f3d-ac5eee68aa18 (Autodesk Fusion 360 design; units mm, degrees)
Autodesk Fusion 360 part; units mm, degrees
ref_plane "WorkPlane1" through (0, 0, 0) normal (0, 1, 0) x (0, 0, 1) in component "ДСП 16 — горизонталь"
sketch "Sketch1" plane through (0, 0, 0) normal (0, 1, 0) x (1, 0, 0) in component "ДСП 16 — горизонталь"
  line L0 (150, -2) -> (850, -2)
  arc A0 (850, -298) -> (850, -2) centre (850, -150) ccw
  line L1 (850, -298) -> (150, -298)
  arc A1 (150, -2) -> (150, -298) centre (150, -150) ccw
extrude "ДСП 16 — горизонталь" add sketch "Sketch1" along normal blind 16 makes body 1 in component "ДСП 16 — горизонталь"
ref_plane "WorkPlane2" through (0, 0, 0) normal (0, 1, 0) x (0, 0, 1) in component "ДСП 16 — горизонталь"
sketch "Sketch2" plane through (0, 0, 0) normal (0, 1, 0) x (1, 0, 0) in component "ДСП 16 — горизонталь"
  line L0 (208.1, 3) -> (208.1, -37)
  line L1 (208.1, -37) -> (191.9, -37)
  line L2 (191.9, -37) -> (191.9, 3)
  line L3 (191.9, 3) -> (208.1, 3)
  line L4 (408.1, 3) -> (408.1, -37)
  line L5 (408.1, -37) -> (391.9, -37)
  line L6 (391.9, -37) -> (391.9, 3)
  line L7 (391.9, 3) -> (408.1, 3)
  line L8 (499.1, 3) -> (499.1, -37)
  line L9 (499.1, -37) -> (482.9, -37)
  line L10 (482.9, -37) -> (482.9, 3)
  line L11 (482.9, 3) -> (499.1, 3)
  line L12 (517.1, 3) -> (517.1, -37)
  line L13 (517.1, -37) -> (500.9, -37)
  line L14 (500.9, -37) -> (500.9, 3)
  line L15 (500.9, 3) -> (517.1, 3)
  line L16 (608.1, 3) -> (608.1, -37)
  line L17 (608.1, -37) -> (591.9, -37)
  line L18 (591.9, -37) -> (591.9, 3)
  line L19 (591.9, 3) -> (608.1, 3)
  line L20 (808.1, 3) -> (808.1, -37)
  line L21 (808.1, -37) -> (791.9, -37)
  line L22 (791.9, -37) -> (791.9, 3)
  line L23 (791.9, 3) -> (808.1, 3)
  line L24 (191.9, -303) -> (191.9, -263)
  line L25 (191.9, -263) -> (208.1, -263)
  line L26 (208.1, -263) -> (208.1, -303)
  line L27 (208.1, -303) -> (191.9, -303)
  line L28 (391.9, -303) -> (391.9, -263)
  line L29 (391.9, -263) -> (408.1, -263)
  line L30 (408.1, -263) -> (408.1, -303)
  line L31 (408.1, -303) -> (391.9, -303)
  line L32 (482.9, -303) -> (482.9, -263)
  line L33 (482.9, -263) -> (499.1, -263)
  line L34 (499.1, -263) -> (499.1, -303)
  line L35 (499.1, -303) -> (482.9, -303)
  line L36 (500.9, -303) -> (500.9, -263)
  line L37 (500.9, -263) -> (517.1, -263)
  line L38 (517.1, -263) -> (517.1, -303)
  line L39 (517.1, -303) -> (500.9, -303)
  line L40 (591.9, -303) -> (591.9, -263)
  line L41 (591.9, -263) -> (608.1, -263)
  line L42 (608.1, -263) -> (608.1, -303)
  line L43 (608.1, -303) -> (591.9, -303)
  line L44 (791.9, -303) -> (791.9, -263)
  line L45 (791.9, -263) -> (808.1, -263)
  line L46 (808.1, -263) -> (808.1, -303)
  line L47 (808.1, -303) -> (791.9, -303)
  line L48 (933.5148, -21.5481) -> (913.5148, -56.1891)
  line L49 (913.5148, -56.1891) -> (899.4852, -48.0891)
  line L50 (899.4852, -48.0891) -> (919.4852, -13.4481)
  line L51 (919.4852, -13.4481) -> (933.5148, -21.5481)
  line L52 (1003, -158.1) -> (963, -158.1)
  line L53 (963, -158.1) -> (963, -141.9)
  line L54 (963, -141.9) -> (1003, -141.9)
  line L55 (1003, -141.9) -> (1003, -158.1)
  line L56 (919.4852, -286.5519) -> (899.4852, -251.9109)
  line L57 (899.4852, -251.9109) -> (913.5148, -243.8109)
  line L58 (913.5148, -243.8109) -> (933.5148, -278.4519)
  line L59 (933.5148, -278.4519) -> (919.4852, -286.5519)
  line L60 (66.4852, -278.4519) -> (86.4852, -243.8109)
  line L61 (86.4852, -243.8109) -> (100.5148, -251.9109)
  line L62 (100.5148, -251.9109) -> (80.5148, -286.5519)
  line L63 (80.5148, -286.5519) -> (66.4852, -278.4519)
  line L64 (-3, -141.9) -> (37, -141.9)
  line L65 (37, -141.9) -> (37, -158.1)
  line L66 (37, -158.1) -> (-3, -158.1)
  line L67 (-3, -158.1) -> (-3, -141.9)
  line L68 (80.5148, -13.4481) -> (100.5148, -48.0891)
  line L69 (100.5148, -48.0891) -> (86.4852, -56.1891)
  line L70 (86.4852, -56.1891) -> (66.4852, -21.5481)
  line L71 (66.4852, -21.5481) -> (80.5148, -13.4481)
extrude "Пазы 16,2 мм (1)" cut sketch "Sketch2" along normal blind 16 contours L0 L1 L2 L3 | L20 L21 L22 L23 | L24 L25 L26 L27 | L44 L45 L46 L47 | L48 L49 L50 L51 | L52 L53 L54 L55 | L56 L57 L58 L59 | L60 L61 L62 L63 | L64 L65 L66 L67 | L68 L69 L70 L71 bodies 1 in component "ДСП 16 — горизонталь"
ref_plane "WorkPlane3" through (0, 0, 0) normal (0, 1, 0) x (0, 0, 1) in component "ДСП 16 — горизонталь"
sketch "Sketch3" plane through (0, 0, 0) normal (0, 1, 0) x (1, 0, 0) in component "ДСП 16 — горизонталь"
  circle A0 centre (206.9686, -35.8686) radius 1.6
  circle A1 centre (193.0314, -35.8686) radius 1.6
  circle A2 centre (406.9686, -35.8686) radius 1.6
  circle A3 centre (393.0314, -35.8686) radius 1.6
  circle A4 centre (497.9686, -35.8686) radius 1.6
  circle A5 centre (484.0314, -35.8686) radius 1.6
  circle A6 centre (515.9686, -35.8686) radius 1.6
  circle A7 centre (502.0314, -35.8686) radius 1.6
  circle A8 centre (606.9686, -35.8686) radius 1.6
  circle A9 centre (593.0314, -35.8686) radius 1.6
  circle A10 centre (806.9686, -35.8686) radius 1.6
  circle A11 centre (793.0314, -35.8686) radius 1.6
  circle A12 centre (193.0314, -264.1314) radius 1.6
  circle A13 centre (206.9686, -264.1314) radius 1.6
  circle A14 centre (393.0314, -264.1314) radius 1.6
  circle A15 centre (406.9686, -264.1314) radius 1.6
  circle A16 centre (484.0314, -264.1314) radius 1.6
  circle A17 centre (497.9686, -264.1314) radius 1.6
  circle A18 centre (502.0314, -264.1314) radius 1.6
  circle A19 centre (515.9686, -264.1314) radius 1.6
  circle A20 centre (593.0314, -264.1314) radius 1.6
  circle A21 centre (606.9686, -264.1314) radius 1.6
  circle A22 centre (793.0314, -264.1314) radius 1.6
  circle A23 centre (806.9686, -264.1314) radius 1.6
  circle A24 centre (913.1007, -54.6436) radius 1.6
  circle A25 centre (901.0307, -47.675) radius 1.6
  circle A26 centre (964.1314, -156.9686) radius 1.6
  circle A27 centre (964.1314, -143.0314) radius 1.6
  circle A28 centre (901.0307, -252.325) radius 1.6
  circle A29 centre (913.1007, -245.3564) radius 1.6
  circle A30 centre (86.8993, -245.3564) radius 1.6
  circle A31 centre (98.9693, -252.325) radius 1.6
  circle A32 centre (35.8686, -143.0314) radius 1.6
  circle A33 centre (35.8686, -156.9686) radius 1.6
  circle A34 centre (98.9693, -47.675) radius 1.6
  circle A35 centre (86.8993, -54.6436) radius 1.6
extrude "Догбоны Ø3,2 мм (1)" cut sketch "Sketch3" along normal blind 16 contours A0 | A1 | A10 | A11 | A12 | A13 | A22 | A23 | A24 | A25 | A26 | A27 | A28 | A29 | A30 | A31 | A32 | A33 | A34 | A35 bodies 1 in component "ДСП 16 — горизонталь"
ref_plane "WorkPlane1" through (0, 982, 0) normal (0, 1, 0) x (0, 0, 1) in component "ДСП 16 — верхнее кольцо"
sketch "Sketch1 (2)" plane through (0, 982, 0) normal (0, 1, 0) x (1, 0, 0) in component "ДСП 16 — верхнее кольцо"
  line L0 (150, -2) -> (850, -2)
  arc A0 (850, -298) -> (850, -2) centre (850, -150) ccw
  line L1 (850, -298) -> (150, -298)
  arc A1 (150, -2) -> (150, -298) centre (150, -150) ccw
  line L2 (150, -30) -> (850, -30)
  arc A2 (850, -270) -> (850, -30) centre (850, -150) ccw
  line L3 (850, -270) -> (150, -270)
  arc A3 (150, -30) -> (150, -270) centre (150, -150) ccw
extrude "ДСП 16 — верхнее кольцо" add sketch "Sketch1 (2)" along normal blind 16 separate body makes body 2 in component "ДСП 16 — верхнее кольцо"
ref_plane "WorkPlane1" through (0, 850, 0) normal (0, 1, 0) x (0, 0, 1) in component "ДСП 16 — дно ниши"
sketch "Sketch1 (3)" plane through (0, 850, 0) normal (0, 1, 0) x (1, 0, 0) in component "ДСП 16 — дно ниши"
  line L0 (150, -30) -> (850, -30)
  arc A0 (850, -270) -> (850, -30) centre (850, -150) ccw
  line L1 (850, -270) -> (150, -270)
  arc A1 (150, -30) -> (150, -270) centre (150, -150) ccw
extrude "ДСП 16 — дно ниши" add sketch "Sketch1 (3)" along normal blind 16 separate body makes body 3 in component "ДСП 16 — дно ниши"
ref_plane "WorkPlane1" through (0, 0, -8) normal (0, 0, 1) x (1, 0, 0) in component "ДСП 16 — ламель"
sketch "Sketch1 (4)" plane through (0, 0, -8) normal (0, 0, 1) x (1, 0, 0) in component "ДСП 16 — ламель"
  line L0 (0, 0) -> (35, 0)
  line L1 (35, 0) -> (35, 16.1)
  line L2 (35, 16.1) -> (70, 16.1)
  line L3 (70, 16.1) -> (70, 490.9)
  line L4 (70, 490.9) -> (35, 490.9)
  line L5 (35, 490.9) -> (35, 507.1)
  line L6 (35, 507.1) -> (70, 507.1)
  line L7 (70, 507.1) -> (70, 850)
  line L8 (70, 850) -> (28, 850)
  line L9 (28, 850) -> (28, 982)
  line L10 (28, 982) -> (0, 982)
  line L11 (0, 982) -> (0, 0)
extrude "ДСП 16 — ламель" add sketch "Sketch1 (4)" along normal blind 16 separate body makes body 4 in component "ДСП 16 — ламель"
ref_plane "WorkPlane2" through (0, 0, -8) normal (0, 0, 1) x (1, 0, 0) in component "ДСП 16 — ламель"
sketch "Sketch2 (2)" plane through (0, 0, -8) normal (0, 0, 1) x (1, 0, 0) in component "ДСП 16 — ламель"
  circle A0 centre (36.1314, 14.9686) radius 1.6
  circle A1 centre (36.1314, 492.0314) radius 1.6
  circle A2 centre (36.1314, 505.9686) radius 1.6
extrude "Догбоны Ø3,2 мм (2)" cut sketch "Sketch2 (2)" along normal blind 16 sketch seen with x (0, 0, 1) y (0, 1, 0) z (-1, 0, 0) at (200, 0, 2) bodies 1 in component "ДСП 16 — горизонталь"
extrude "Extrude2" cut sketch "Sketch2 (2)" along normal blind 16 bodies 4 in component "ДСП 16 — ламель"
ref_plane "WorkPlane1" through (0, 0, -8) normal (0, 0, 1) x (1, 0, 0) in component "ДСП 16 — ламель радиусная"
sketch "Sketch1 (5)" plane through (0, 0, -8) normal (0, 0, 1) x (1, 0, 0) in component "ДСП 16 — ламель радиусная"
  line L0 (0, 0) -> (35, 0)
  line L1 (35, 0) -> (35, 16.1)
  line L2 (35, 16.1) -> (70, 16.1)
  line L3 (70, 16.1) -> (70, 490.9)
  line L4 (70, 490.9) -> (35, 490.9)
  line L5 (35, 490.9) -> (35, 507.1)
  line L6 (35, 507.1) -> (70, 507.1)
  line L7 (70, 507.1) -> (70, 850)
  line L8 (70, 850) -> (28, 850)
  line L9 (28, 850) -> (28, 982)
  line L10 (28, 982) -> (0, 982)
  line L11 (0, 982) -> (0, 0)
extrude "ДСП 16 — ламель радиусная" add sketch "Sketch1 (5)" along normal blind 16 separate body makes body 5 in component "ДСП 16 — ламель радиусная"
ref_plane "WorkPlane2" through (0, 0, -8) normal (0, 0, 1) x (1, 0, 0) in component "ДСП 16 — ламель радиусная"
sketch "Sketch2 (3)" plane through (0, 0, -8) normal (0, 0, 1) x (1, 0, 0) in component "ДСП 16 — ламель радиусная"
  circle A0 centre (36.1314, 14.9686) radius 1.6
  circle A1 centre (36.1314, 492.0314) radius 1.6
  circle A2 centre (36.1314, 505.9686) radius 1.6
extrude "Догбоны Ø3,2 мм (3)" cut sketch "Sketch2 (3)" along normal blind 16 sketch seen with x (-0.5, 0, 0.866025) y (0, 1, 0) z (-0.866025, 0, -0.5) at (924, 0, 21.8282) bodies 1 in component "ДСП 16 — горизонталь"
extrude "Extrude2'" cut sketch "Sketch2 (3)" along normal blind 16 bodies 5 in component "ДСП 16 — ламель радиусная"
ref_plane "WorkPlane3" through (0, 0, 0) normal (0, 1, 0) x (0, 0, 1) in component "ДСП 16 — ламель радиусная"
sketch "Sketch3 (2)" plane through (0, 0, 0) normal (0, 1, 0) x (1, 0, 0) in component "ДСП 16 — ламель радиусная"
  line L0 (-10, 8) -> (0.2164, 8)
  arc A0 (0.2164, 8) -> (0.2164, -8) centre (148, 0) ccw
  line L1 (0.2164, -8) -> (-10, -8)
  line L2 (-10, -8) -> (-10, 8)
extrude "Подгонка по радиусу (1)" cut sketch "Sketch3 (2)" along normal blind 982 bodies 5 in component "ДСП 16 — ламель радиусная"
ref_plane "WorkPlane1" through (0, 0, 0) normal (0, 1, 0) x (0, 0, 1) in component "ПС 2 — наружная обшивка"
sketch "Sketch1 (6)" plane through (0, 0, 0) normal (0, 1, 0) x (1, 0, 0) in component "ПС 2 — наружная обшивка"
  line L0 (150, 0) -> (850, 0)
  arc A0 (850, -300) -> (850, 0) centre (850, -150) ccw
  line L1 (850, -300) -> (150, -300)
  arc A1 (150, 0) -> (150, -300) centre (150, -150) ccw
  line L2 (150, -2) -> (850, -2)
  arc A2 (850, -298) -> (850, -2) centre (850, -150) ccw
  line L3 (850, -298) -> (150, -298)
  arc A3 (150, -2) -> (150, -298) centre (150, -150) ccw
extrude "ПС 2 — наружная обшивка" add sketch "Sketch1 (6)" along normal blind 998 separate body makes body 6 in component "ПС 2 — наружная обшивка"
ref_plane "WorkPlane2" through (500, 0, 0) normal (1, 0, 0) x (0, 1, 0) in component "ПС 2 — наружная обшивка"
split "Прямые стыки" by plane through (500, 0, 0) normal (1, 0, 0) bodies 6 makes body 7 at (887.0136, 665.3333, 4.6384) in component "ПС 2 — наружная обшивка"
ref_plane "WorkPlane1" through (0, 866, 0) normal (0, 1, 0) x (0, 0, 1) in component "ПС 2 — внутренняя обшивка"
sketch "Sketch1 (7)" plane through (0, 866, 0) normal (0, 1, 0) x (1, 0, 0) in component "ПС 2 — внутренняя обшивка"
  line L0 (150, -30) -> (850, -30)
  arc A0 (850, -270) -> (850, -30) centre (850, -150) ccw
  line L1 (850, -270) -> (150, -270)
  arc A1 (150, -30) -> (150, -270) centre (150, -150) ccw
  line L2 (150, -32) -> (850, -32)
  arc A2 (850, -268) -> (850, -32) centre (850, -150) ccw
  line L3 (850, -268) -> (150, -268)
  arc A3 (150, -32) -> (150, -268) centre (150, -150) ccw
extrude "ПС 2 — внутренняя обшивка" add sketch "Sketch1 (7)" along normal blind 132 separate body makes body 8 in component "ПС 2 — внутренняя обшивка"
ref_plane "WorkPlane2" through (500, 0, 0) normal (1, 0, 0) x (0, 1, 0) in component "ПС 2 — внутренняя обшивка"
split "Прямые стыки'" by plane through (500, 0, 0) normal (1, 0, 0) bodies 8 makes body 9 at (912.5722, 910, 47.6051) in component "ПС 2 — внутренняя обшивка"
ref_plane "WorkPlane1" through (0, 998, 0) normal (0, 1, 0) x (0, 0, 1) in component "ПС 2 — верхнее кольцо"
sketch "Sketch1 (8)" plane through (0, 998, 0) normal (0, 1, 0) x (1, 0, 0) in component "ПС 2 — верхнее кольцо"
  line L0 (150, 0) -> (850, 0)
  arc A0 (850, -300) -> (850, 0) centre (850, -150) ccw
  line L1 (850, -300) -> (150, -300)
  arc A1 (150, 0) -> (150, -300) centre (150, -150) ccw
  line L2 (150, -32) -> (850, -32)
  arc A2 (850, -268) -> (850, -32) centre (850, -150) ccw
  line L3 (850, -268) -> (150, -268)
  arc A3 (150, -32) -> (150, -268) centre (150, -150) ccw
extrude "ПС 2 — верхнее кольцо" add sketch "Sketch1 (8)" along normal blind 2 separate body makes body 10 in component "ПС 2 — верхнее кольцо"
ref_plane "WorkPlane4" through (0, 0, 0) normal (0, 1, 0) x (0, 0, 1) in component "ДСП 16 — горизонталь"
sketch "Sketch4" plane through (0, 0, 0) normal (0, 1, 0) x (1, 0, 0) in component "ДСП 16 — горизонталь"
  line L0 (483.9, 3) -> (516.1, 3)
  line L1 (516.1, 3) -> (516.1, -37)
  line L2 (516.1, -37) -> (483.9, -37)
  line L3 (483.9, -37) -> (483.9, 3)
  line L4 (483.9, -303) -> (516.1, -303)
  line L5 (516.1, -303) -> (516.1, -263)
  line L6 (516.1, -263) -> (483.9, -263)
  line L7 (483.9, -263) -> (483.9, -303)
extrude "Парные ламели — паз 32,2 мм (1)" cut sketch "Sketch4" along normal blind 16 bodies 1 in component "ДСП 16 — горизонталь"
ref_plane "WorkPlane5" through (0, 0, 0) normal (0, 1, 0) x (0, 0, 1) in component "ДСП 16 — горизонталь"
sketch "Sketch5" plane through (0, 0, 0) normal (0, 1, 0) x (1, 0, 0) in component "ДСП 16 — горизонталь"
  circle A0 centre (485.0314, -35.8686) radius 1.6
  circle A1 centre (514.9686, -35.8686) radius 1.6
  circle A2 centre (485.0314, -264.1314) radius 1.6
  circle A3 centre (514.9686, -264.1314) radius 1.6
extrude "Парные ламели — догбоны Ø3,2 мм (1)" cut sketch "Sketch5" along normal blind 16 bodies 1 in component "ДСП 16 — горизонталь"
component "Кашпо" placed x (1, 0, 0) y (0, 1, 0) z (0, 0, 1) at (0, 0, 0)
component "ДСП 16 — горизонталь" placed x (1, 0, 0) y (0, 1, 0) z (0, 0, 1) at (0, 0, 0) in component "Кашпо"
component "ДСП 16 — верхнее кольцо" placed x (1, 0, 0) y (0, 1, 0) z (0, 0, 1) at (0, 0, 0) in component "Кашпо"
component "ДСП 16 — дно ниши" placed x (1, 0, 0) y (0, 1, 0) z (0, 0, 1) at (0, 0, 0) in component "Кашпо"
component "ДСП 16 — ламель" placed x (0, 0, 1) y (0, 1, 0) z (-1, 0, 0) at (200, 0, 2) in component "Кашпо"
component "ДСП 16 — ламель радиусная" placed x (-0.5, 0, 0.866025) y (0, 1, 0) z (-0.866025, 0, -0.5) at (924, 0, 21.8282) in component "Кашпо"
component "ПС 2 — наружная обшивка" placed x (1, 0, 0) y (0, 1, 0) z (0, 0, 1) at (0, 0, 0) in component "Кашпо"
component "ПС 2 — внутренняя обшивка" placed x (1, 0, 0) y (0, 1, 0) z (0, 0, 1) at (0, 0, 0) in component "Кашпо"
component "ПС 2 — верхнее кольцо" placed x (1, 0, 0) y (0, 1, 0) z (0, 0, 1) at (0, 0, 0) in component "Кашпо"
component "ДСП 16 — горизонталь" placed x (1, 0, 0) y (0, 1, 0) z (0, 0, 1) at (0, 491, 0) in component "Кашпо"
component "ДСП 16 — ламель" placed x (0, 0, 1) y (0, 1, 0) z (-1, 0, 0) at (492, 0, 2) in component "Кашпо"
component "ДСП 16 — ламель" placed x (0, 0, 1) y (0, 1, 0) z (-1, 0, 0) at (508, 0, 2) in component "Кашпо"
component "ДСП 16 — ламель" placed x (0, 0, 1) y (0, 1, 0) z (-1, 0, 0) at (800, 0, 2) in component "Кашпо"
component "ДСП 16 — ламель" placed x (0, 0, -1) y (0, 1, 0) z (1, 0, 0) at (200, 0, 298) in component "Кашпо"
component "ДСП 16 — ламель" placed x (0, 0, -1) y (0, 1, 0) z (1, 0, 0) at (492, 0, 298) in component "Кашпо"
component "ДСП 16 — ламель" placed x (0, 0, -1) y (0, 1, 0) z (1, 0, 0) at (508, 0, 298) in component "Кашпо"
component "ДСП 16 — ламель" placed x (0, 0, -1) y (0, 1, 0) z (1, 0, 0) at (800, 0, 298) in component "Кашпо"
component "ДСП 16 — ламель радиусная" placed x (-1, 0, 0) y (0, 1, 0) z (0, 0, -1) at (998, 0, 150) in component "Кашпо"
component "ДСП 16 — ламель радиусная" placed x (-0.5, 0, -0.866025) y (0, 1, 0) z (0.866025, 0, -0.5) at (924, 0, 278.1718) in component "Кашпо"
component "ДСП 16 — ламель радиусная" placed x (0.5, 0, -0.866025) y (0, 1, 0) z (0.866025, 0, 0.5) at (76, 0, 278.1718) in component "Кашпо"
component "ДСП 16 — ламель радиусная" placed x (1, 0, 0) y (0, 1, 0) z (0, 0, 1) at (2, 0, 150) in component "Кашпо"
component "ДСП 16 — ламель радиусная" placed x (0.5, 0, 0.866025) y (0, 1, 0) z (-0.866025, 0, 0.5) at (76, 0, 21.8282) in component "Кашпо"
component "Первый трест кашпо — вариант 2 v4" placed x (1, 0, 0) y (0, 1, 0) z (0, 0, 1) at (0, 0, 0) in component "ДСП 16 — дно ниши"
named bodies: "ДСП 16 — горизонталь", "ДСП 16 — верхнее кольцо", "ДСП 16 — дно ниши", "ДСП 16 — ламель", "ДСП 16 — ламель радиусная", "ПС 2 — наружная обшивка — часть 1", "ПС 2 — наружная обшивка — часть 2", "ПС 2 — внутренняя обшивка — часть 1", "ПС 2 — внутренняя обшивка — часть 2", "ПС 2 — верхнее кольцо"
